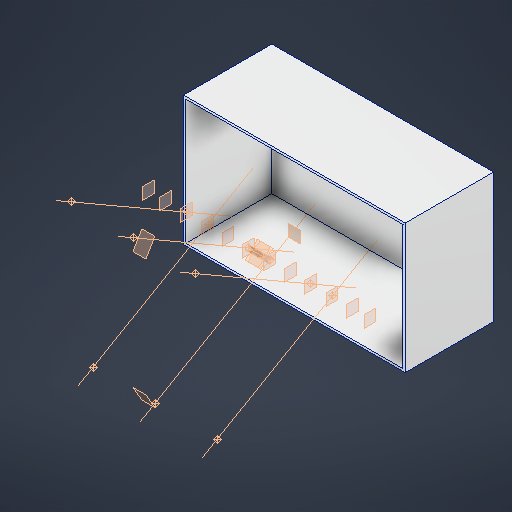
# Autodesk Inventor part: Oil_Pan_SIMPLIFIED
Saved by Autodesk Inventor 2027.1 (Build 311270010, 270A)
## iProperties
Created: 2026-10-17
Part Number: Oil_Pan_SIMPLIFIED
Material: Aluminum 6061
Document SubType Name: Modeling
Designer: kashyap
Density: 2.7 g/cm^3
Appearance: Aluminum - Flat
Mass: 2750.46 g
Surface Area: 5141.16 cm^2
Volume: 1018.69 cm^3
Material_Status: Assumed for this reconstruction
Author: kashyap
Autodesk Inventor part; units mm, degrees
ref_plane "YZ Plane" through (0, 0, 0) normal (1, 0, 0) x (0, 1, 0)
ref_plane "XZ Plane" through (0, 0, 0) normal (0, 1, 0) x (-1, 0, 0)
ref_plane "XY Plane" through (0, 0, 0) normal (0, 0, 1) x (1, 0, 0)
derived "V6_Engine_Master.ipt"
ref_plane "Bank_A_Plane" through (0, 0, 0) normal (0, 0.8660254, -0.5) x (-1, 0, 0)
ref_plane "Bank_B_Plane" through (0, 0, 0) normal (0, 0.8660254, 0.5) x (-1, 0, 0)
ref_plane "Bank_A_Perp_Plane" through (0, 0, 0) normal (0, 0.5, 0.8660254) x (-1, 0, 0)
ref_plane "Bank_B_Perp_Plane" through (0, 0, 0) normal (0, -0.5, 0.8660254) x (-1, 0, 0)
ref_plane "Bank_A_Deck_Plane" through (0, 112.9, 195.5485) normal (0, 0.5, 0.8660254) x (-1, 0, 0)
ref_plane "Bank_B_Deck_Plane" through (0, -112.9, 195.5485) normal (0, -0.5, 0.8660254) x (-1, 0, 0)
ref_plane "Cyl_A1_Station_Plane" through (-123.8, 0, 0) normal (1, 0, 0) x (0, 1, 0)
ref_plane "Cyl_A2_Station_Plane" through (-18.3, 0, 0) normal (1, 0, 0) x (0, 1, 0)
ref_plane "Cyl_A3_Station_Plane" through (87.2, 0, 0) normal (1, 0, 0) x (0, 1, 0)
ref_plane "Cyl_B1_Station_Plane" through (-87.2, 0, 0) normal (1, 0, 0) x (0, 1, 0)
ref_plane "Cyl_B2_Station_Plane" through (18.3, 0, 0) normal (1, 0, 0) x (0, 1, 0)
ref_plane "Cyl_B3_Station_Plane" through (123.8, 0, 0) normal (1, 0, 0) x (0, 1, 0)
ref_plane "Main_Bearing_Station_1" through (-158.25, 0, 0) normal (1, 0, 0) x (0, 1, 0)
ref_plane "Main_Bearing_Station_2" through (-52.75, 0, 0) normal (1, 0, 0) x (0, 1, 0)
ref_plane "Main_Bearing_Station_3" through (52.75, 0, 0) normal (1, 0, 0) x (0, 1, 0)
ref_plane "Main_Bearing_Station_4" through (158.25, 0, 0) normal (1, 0, 0) x (0, 1, 0)
ref_plane "Front_Interface" through (-188.25, 0, 0) normal (1, 0, 0) x (0, 1, 0)
ref_plane "Rear_Interface" through (188.25, 0, 0) normal (1, 0, 0) x (0, 1, 0)
ref_plane "Oil_Pan_Plane" through (0, 0, -60) normal (0, 0, 1) x (1, 0, 0)
sketch "SK_Pan_Shell" plane through (0, 0, -60) normal (0, 0, 1) x (1, 0, 0)
  line L0 (-188.25, -110) -> (188.25, -110)
  line L1 (188.25, -110) -> (188.25, 110)
  line L2 (188.25, 110) -> (-188.25, 110)
  line L3 (-188.25, 110) -> (-188.25, -110)
  constraints: 8 end point, 2 parallel, 1 horizontal, 1 perpendicular
extrude "Pan_Shell" add sketch "SK_Pan_Shell" against normal blind 150
sketch "SK_Pan_Cavity" plane through (0, 0, -60) normal (0, 0, 1) x (1, 0, 0)
  line L0 (-184.25, -106) -> (184.25, -106)
  line L1 (184.25, -106) -> (184.25, 106)
  line L2 (184.25, 106) -> (-184.25, 106)
  line L3 (-184.25, 106) -> (-184.25, -106)
  constraints: 8 end point, 2 parallel, 1 horizontal, 1 perpendicular
extrude "Pan_Cavity" cut sketch "SK_Pan_Cavity" against normal blind 146
equation "\"d21\" = Oil_Pan_Depth"
equation "\"d25\" = Oil_Pan_Depth - Oil_Pan_Wall"
equation "\"Oil_Pan_Depth\" = 150"
equation "\"Oil_Pan_Wall\" = 4"
body "Solid2"
